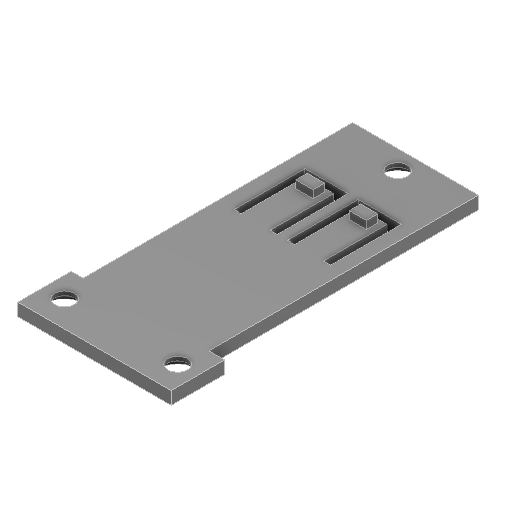
# Autodesk Inventor part: PRT - 9041 - CAMTARCOV - V04
Saved by Autodesk Inventor 2025.5 (Build 295498000, 498)
## iProperties
Created: 2026-11-06
Part Number: PRT - 9041 - CAMTARCOV - V04
Material: Generisch
Description: Back cover: lies in a recess of the back, tongues press the XIAO forward, the slits are the vents. Three M3 x 10 into Ruthex inserts. Print on the back face.
Document SubType Name: Modeling
Designer: benir
Density: 1 g/cm^3
Appearance: Smooth - Dark Gray
Author: benir
Autodesk Inventor part; units mm, degrees
ref_plane "y=back_y" through (0, -16.8, 0) normal (0, 1, 0) x (-1, 0, 0)
sketch "cover sketch" plane through (0, -16.8, 0) normal (0, 1, 0) x (-1, 0, 0)
  line L0 (11.7, -24.2) -> (-10, -24.2)
  line L1 (-10, -24.2) -> (-10, 22.3)
  line L2 (-10, 22.3) -> (-12.7, 22.3)
  line L3 (-12.7, 22.3) -> (-12.7, 31.5)
  line L4 (-12.7, 31.5) -> (13.75, 31.5)
  line L5 (13.75, 31.5) -> (13.75, 22.3)
  line L6 (13.75, 22.3) -> (11.7, 22.3)
  line L7 (11.7, 22.3) -> (11.7, -24.2)
  point P0 (0, 0)
  dimension "d1" = 24.2
  dimension "d2" = 11.7
  dimension "d3" = 24.2
  dimension "d4" = 10
  dimension "d5" = 22.3
  dimension "d6" = 10
  dimension "d7" = 22.3
  dimension "d8" = 12.7
  dimension "d9" = 31.5
  dimension "d10" = 12.7
  dimension "d11" = 31.5
  dimension "d12" = 13.75
  dimension "d13" = 22.3
  dimension "d14" = 13.75
  dimension "d15" = 22.3
  dimension "d16" = 11.7
  constraints: 16 end point
  measures "d1" vertical distance of point (0, 0) L0.start
  measures "d2" horizontal distance of point (0, 0) L0.start
  measures "d3" vertical distance of point (0, 0) L0.end
  measures "d4" horizontal distance of point (0, 0) L0.end
  measures "d5" vertical distance of point (0, 0) L1.end
  measures "d6" horizontal distance of point (0, 0) L1.end
  measures "d7" vertical distance of point (0, 0) L2.end
  measures "d8" horizontal distance of point (0, 0) L2.end
  measures "d9" vertical distance of point (0, 0) L3.end
  measures "d10" horizontal distance of point (0, 0) L3.end
  measures "d11" vertical distance of point (0, 0) L4.end
  measures "d12" horizontal distance of point (0, 0) L4.end
  measures "d13" vertical distance of point (0, 0) L5.end
  measures "d14" horizontal distance of point (0, 0) L5.end
  measures "d15" vertical distance of point (0, 0) L6.end
  measures "d16" horizontal distance of point (0, 0) L6.end
extrude "cover plate" add sketch "cover sketch" along normal blind 2.2
ref_plane "y=back_y - 1 mm" through (0, -17.8, 0) normal (0, 1, 0) x (-1, 0, 0)
sketch "tongue sketch" plane through (0, -17.8, 0) normal (0, 1, 0) x (-1, 0, 0)
  line L0 (8.93, -1) -> (8.93, -13.2)
  line L1 (8.93, -13.2) -> (1.53, -13.2)
  line L2 (1.53, -13.2) -> (1.53, -1)
  line L3 (1.53, -1) -> (2.73, -1)
  line L4 (2.73, -1) -> (2.73, -12)
  line L5 (2.73, -12) -> (7.73, -12)
  line L6 (7.73, -12) -> (7.73, -1)
  line L7 (7.73, -1) -> (8.93, -1)
  line L8 (-0.27, -1) -> (-0.27, -13.2)
  line L9 (-0.27, -13.2) -> (-7.67, -13.2)
  line L10 (-7.67, -13.2) -> (-7.67, -1)
  line L11 (-7.67, -1) -> (-6.47, -1)
  line L12 (-6.47, -1) -> (-6.47, -12)
  line L13 (-6.47, -12) -> (-1.47, -12)
  line L14 (-1.47, -12) -> (-1.47, -1)
  line L15 (-1.47, -1) -> (-0.27, -1)
  point P0 (0, 0)
  dimension "d20" = 1
  dimension "d21" = 8.93
  dimension "d22" = 13.2
  dimension "d23" = 8.93
  dimension "d24" = 13.2
  dimension "d25" = 1.53
  dimension "d26" = 1
  dimension "d27" = 1.53
  dimension "d28" = 1
  dimension "d29" = 2.73
  dimension "d30" = 12
  dimension "d31" = 2.73
  dimension "d32" = 12
  dimension "d33" = 7.73
  dimension "d34" = 1
  dimension "d35" = 7.73
  dimension "d36" = 1
  dimension "d37" = 0.27
  dimension "d38" = 13.2
  dimension "d39" = 0.27
  dimension "d40" = 13.2
  dimension "d41" = 7.67
  dimension "d42" = 1
  dimension "d43" = 7.67
  dimension "d44" = 1
  dimension "d45" = 6.47
  dimension "d46" = 12
  dimension "d47" = 6.47
  dimension "d48" = 12
  dimension "d49" = 1.47
  dimension "d50" = 1
  dimension "d51" = 1.47
  constraints: 32 end point
  measures "d20" vertical distance of point (0, 0) L0.start
  measures "d21" horizontal distance of point (0, 0) L0.start
  measures "d22" vertical distance of point (0, 0) L0.end
  measures "d23" horizontal distance of point (0, 0) L0.end
  measures "d24" vertical distance of point (0, 0) L1.end
  measures "d25" horizontal distance of point (0, 0) L1.end
  measures "d26" vertical distance of point (0, 0) L2.end
  measures "d27" horizontal distance of point (0, 0) L2.end
  measures "d28" vertical distance of point (0, 0) L3.end
  measures "d29" horizontal distance of point (0, 0) L3.end
  measures "d30" vertical distance of point (0, 0) L4.end
  measures "d31" horizontal distance of point (0, 0) L4.end
  measures "d32" vertical distance of point (0, 0) L5.end
  measures "d33" horizontal distance of point (0, 0) L5.end
  measures "d34" vertical distance of point (0, 0) L6.end
  measures "d35" horizontal distance of point (0, 0) L6.end
  measures "d36" vertical distance of point (0, 0) L8.start
  measures "d37" horizontal distance of point (0, 0) L8.start
  measures "d38" vertical distance of point (0, 0) L8.end
  measures "d39" horizontal distance of point (0, 0) L8.end
  measures "d40" vertical distance of point (0, 0) L9.end
  measures "d41" horizontal distance of point (0, 0) L9.end
  measures "d42" vertical distance of point (0, 0) L10.end
  measures "d43" horizontal distance of point (0, 0) L10.end
  measures "d44" vertical distance of point (0, 0) L11.end
  measures "d45" horizontal distance of point (0, 0) L11.end
  measures "d46" vertical distance of point (0, 0) L12.end
  measures "d47" horizontal distance of point (0, 0) L12.end
  measures "d48" vertical distance of point (0, 0) L13.end
  measures "d49" horizontal distance of point (0, 0) L13.end
  measures "d50" vertical distance of point (0, 0) L14.end
  measures "d51" horizontal distance of point (0, 0) L14.end
extrude "spring tongues (the slits are the vents)" cut sketch "tongue sketch" along normal blind 4.2
ref_plane "y=cov_in_y" through (0, -14.6, 0) normal (0, 1, 0) x (-1, 0, 0)
sketch "bump sketch" plane through (0, -14.6, 0) normal (0, 1, 0) x (-1, 0, 0)
  line L0 (6.73, -11.4) -> (3.73, -11.4)
  line L1 (3.73, -11.4) -> (3.73, -9.4)
  line L2 (3.73, -9.4) -> (6.73, -9.4)
  line L3 (6.73, -9.4) -> (6.73, -11.4)
  line L4 (-2.47, -11.4) -> (-5.47, -11.4)
  line L5 (-5.47, -11.4) -> (-5.47, -9.4)
  line L6 (-5.47, -9.4) -> (-2.47, -9.4)
  line L7 (-2.47, -9.4) -> (-2.47, -11.4)
  point P0 (0, 0)
  dimension "d55" = 6.73
  dimension "d56" = 3.73
  dimension "d57" = 11.4
  dimension "d58" = 9.4
  dimension "d59" = 2.47
  dimension "d60" = 5.47
  dimension "d61" = 11.4
  dimension "d62" = 9.4
  constraints: 16 end point, 4 parallel, 2 horizontal, 2 perpendicular
  measures "d55" horizontal distance of point (0, 0) L2.end
  measures "d56" horizontal distance of point (0, 0) L0.end
  measures "d57" vertical distance of point (0, 0) L0.start
  measures "d58" vertical distance of point (0, 0) L1.end
  measures "d59" horizontal distance of point (0, 0) L6.end
  measures "d60" horizontal distance of point (0, 0) L4.end
  measures "d61" vertical distance of point (0, 0) L4.start
  measures "d62" vertical distance of point (0, 0) L5.end
extrude "bumps on the main PCB" add sketch "bump sketch" along normal blind 1.35
sketch "screw sketch" plane through (0, -17.8, 0) normal (0, 1, 0) x (-1, 0, 0)
  circle A0 centre (-9.3, 27) radius 1.7
  circle A1 centre (10.2, 27) radius 1.7
  circle A2 centre (0.63, -20.9) radius 1.7
  point P0 (0, 0)
  dimension "d65" = 27
  dimension "d66" = 9.3
  dimension "d67" = 3.4
  dimension "d68" = 27
  dimension "d69" = 10.2
  dimension "d70" = 3.4
  dimension "d71" = 20.9
  dimension "d72" = 0.63
  dimension "d73" = 3.4
  constraints: 3 centre point
  measures "d65" vertical distance of point (0, 0) A0.centre
  measures "d66" horizontal distance of point (0, 0) A0.centre
  measures "d67" diameter of A0
  measures "d68" vertical distance of point (0, 0) A1.centre
  measures "d69" horizontal distance of point (0, 0) A1.centre
  measures "d70" diameter of A1
  measures "d71" vertical distance of point (0, 0) A2.centre
  measures "d72" horizontal distance of point (0, 0) A2.centre
  measures "d73" diameter of A2
extrude "M3 clearance" cut sketch "screw sketch" along normal blind 4.2
sketch "countersink sketch" plane through (0, -16.8, 0) normal (0, 1, 0) x (-1, 0, 0)
  circle A0 centre (-9.3, 27) radius 3.2
  circle A1 centre (10.2, 27) radius 3.2
  circle A2 centre (0.63, -20.9) radius 3.2
  point P0 (0, 0)
  dimension "d76" = 27
  dimension "d77" = 9.3
  dimension "d78" = 6.4
  dimension "d79" = 27
  dimension "d80" = 10.2
  dimension "d81" = 6.4
  dimension "d82" = 20.9
  dimension "d83" = 0.63
  dimension "d84" = 6.4
  constraints: 3 centre point
  measures "d76" vertical distance of point (0, 0) A0.centre
  measures "d77" horizontal distance of point (0, 0) A0.centre
  measures "d78" diameter of A0
  measures "d79" vertical distance of point (0, 0) A1.centre
  measures "d80" horizontal distance of point (0, 0) A1.centre
  measures "d81" diameter of A1
  measures "d82" vertical distance of point (0, 0) A2.centre
  measures "d83" horizontal distance of point (0, 0) A2.centre
  measures "d84" diameter of A2
extrude "countersinks" cut sketch "countersink sketch" along normal blind 1.5 draft -45
equation "\"d1\" = cov_bot"
equation "\"d2\" = -cov_clr + low_x0"
equation "\"d3\" = cov_bot"
equation "\"d4\" = low_x1 - cov_clr"
equation "\"d5\" = rab_z0 + cov_clr"
equation "\"d6\" = low_x1 - cov_clr"
equation "\"d7\" = rab_z0 + cov_clr"
equation "\"d8\" = rab_x1 - cov_clr"
equation "\"d9\" = cover_top"
equation "\"d10\" = rab_x1 - cov_clr"
equation "\"d11\" = cover_top"
equation "\"d12\" = -cov_clr + rab_x0"
equation "\"d13\" = rab_z0 + cov_clr"
equation "\"d14\" = -cov_clr + rab_x0"
equation "\"d15\" = rab_z0 + cov_clr"
equation "\"d16\" = -cov_clr + low_x0"
equation "\"d17\" = cover_t"
equation "\"d20\" = -ton_z1"
equation "\"d21\" = slit_w + ton_c - usb_x + 0.5 * tongue_w"
equation "\"d22\" = slit_w - ton_z0"
equation "\"d23\" = slit_w + ton_c - usb_x + 0.5 * tongue_w"
equation "\"d24\" = slit_w - ton_z0"
equation "\"d25\" = -slit_w + ton_c - usb_x - 0.5 * tongue_w"
equation "\"d26\" = -ton_z1"
equation "\"d27\" = -slit_w + ton_c - usb_x - 0.5 * tongue_w"
equation "\"d28\" = -ton_z1"
equation "\"d29\" = -0.5 * tongue_w - usb_x + ton_c"
equation "\"d30\" = -ton_z0"
equation "\"d31\" = -0.5 * tongue_w - usb_x + ton_c"
equation "\"d32\" = -ton_z0"
equation "\"d33\" = 0.5 * tongue_w - usb_x + ton_c"
equation "\"d34\" = -ton_z1"
equation "\"d35\" = 0.5 * tongue_w - usb_x + ton_c"
equation "\"d36\" = -ton_z1"
equation "\"d37\" = -0.5 * tongue_w + usb_x + ton_c - slit_w"
equation "\"d38\" = slit_w - ton_z0"
equation "\"d39\" = -0.5 * tongue_w + usb_x + ton_c - slit_w"
equation "\"d40\" = slit_w - ton_z0"
equation "\"d41\" = 0.5 * tongue_w + usb_x + ton_c + slit_w"
equation "\"d42\" = -ton_z1"
equation "\"d43\" = 0.5 * tongue_w + usb_x + ton_c + slit_w"
equation "\"d44\" = -ton_z1"
equation "\"d45\" = ton_c + usb_x + 0.5 * tongue_w"
equation "\"d46\" = -ton_z0"
equation "\"d47\" = ton_c + usb_x + 0.5 * tongue_w"
equation "\"d48\" = -ton_z0"
equation "\"d49\" = ton_c + usb_x - 0.5 * tongue_w"
equation "\"d50\" = -ton_z1"
equation "\"d51\" = ton_c + usb_x - 0.5 * tongue_w"
equation "\"d63\" = bump_y - cov_in_y"
equation "\"d65\" = screw_z"
equation "\"d66\" = screw_x"
equation "\"d67\" = clear_d"
equation "\"d68\" = screw_z"
equation "\"d69\" = screw_x2"
equation "\"d70\" = clear_d"
equation "\"d71\" = screw_z3"
equation "\"d72\" = -usb_x"
equation "\"d73\" = clear_d"
equation "\"d76\" = screw_z"
equation "\"d77\" = screw_x"
equation "\"d78\" = csk_d"
equation "\"d79\" = screw_z"
equation "\"d80\" = screw_x2"
equation "\"d81\" = csk_d"
equation "\"d82\" = screw_z3"
equation "\"d83\" = -usb_x"
equation "\"d84\" = csk_d"
equation "\"d85\" = csk_h"
equation "\"d86\" = -cone_ang"
equation "\"back_y\" = -16.8"
equation "\"d0\" = back_y"
equation "\"low_x0\" = 12"
equation "\"cov_clr\" = 0.3"
equation "\"nose_z\" = 24.4"
equation "\"low_x1\" = 10.3"
equation "\"rab_z0\" = 22"
equation "\"rab_x1\" = 13"
equation "\"cover_top\" = 31.5"
equation "\"rab_x0\" = 14.05"
equation "\"cover_t\" = 2.2"
equation "\"cam_bz\" = -6.75"
equation "\"usb_bz\" = -6.12"
equation "\"usb_x\" = cam_bz - usb_bz"
equation "\"ton_c\" = 4.6"
equation "\"tongue_w\" = 5"
equation "\"slit_w\" = 1.2"
equation "\"ton_z1\" = -1"
equation "\"tongue_l\" = 11"
equation "\"ton_z0\" = ton_z1 - tongue_l"
equation "\"cov_in_y\" = back_y + cover_t"
equation "\"d54\" = cov_in_y"
equation "\"pcb_back_by\" = -0.25"
equation "\"sensor_y\" = -4.5"
equation "\"sensor_by\" = 8.6"
equation "\"ofs_y\" = sensor_y - sensor_by"
equation "\"pcb_back_y\" = pcb_back_by + ofs_y"
equation "\"bump_press\" = 0.1"
equation "\"bump_y\" = pcb_back_y + bump_press"
equation "\"screw_x\" = 9.3"
equation "\"screw_z\" = 27"
equation "\"clear_d\" = 3.4"
equation "\"screw_x2\" = 10.2"
equation "\"screw_z3\" = 20.9"
equation "\"csk_d\" = 6.4"
equation "\"csk_h\" = -0.5 * clear_d + 0.5 * csk_d"
equation "\"cone_ang\" = 45deg"
equation "\"cov_bot\" = 24.2"
body "Solid1"
